Autodesk Fusion 360 part; units mm, degrees
(part 2 of 2)
equation "cass_t_Ref = 34 mm" comment "SOURCE: layout study B1 final list L-CASS 34 (tray + 25 gap + felt 9)"
equation "stack_t_Ref = outer_t_Ref + cav_gap_Ref + cass_t_Ref" comment "CALCULATION: D-16, D-42 stack, walls and ceiling: 46 + 4 + 34 = 84 (was 81 with outer_t 43); the inside is 3 mm smaller per wall and in height"
equation "wall_depth_Ref = 1495 mm" comment "DECIDED: PM ruling pass C: side walls start at the decor back plate (Y -645), as v1 (1496)"
equation "lin_gap_Ref = 4 mm" comment "ASSUMPTION: PM ruling pass C: gap above the upper side linings so they stay floating (= the 4 mm stack gap)"
equation "seam_gap_Ref = 2.26 mm" comment "DECIDED: PM ruling 2026-10-31 (Mechanical Checker F-001, F-005): the Joints Engineer's 2.26 mm at all nine site seam types, set by a metal stop (1.5 stop washer + 0.76 rivnut head; joints register section 2.8)"
equation "wall_z0_Ref = glide_h_Ref + band_h_Ref" comment "CALCULATION: base band top (Z 110)"
equation "panel_z0_Ref = wall_z0_Ref + seam_gap_Ref" comment "CALCULATION: walls stand one seam_gap above the band top (Z 112.26; joints register 2.8, IF-01)"
equation "wall_h_Ref = pod_h_Ref - wall_z0_Ref" comment "CALCULATION: 2290 = layout study v2_model wall_h"
equation "side_h_Ref = ( wall_h_Ref - 2 * seam_gap_Ref ) / 2" comment "CALCULATION: D-23: 2 sheets per side wall; the gap on the band and the horizontal seam (1142.74, was 1145; joints register 2.8)"
equation "pod_h_Ref1 = 2400 mm" comment "DECIDED: D-21 (room floor to roof skin top)"
equation "glide_h_Ref1 = 10 mm" comment "ASSUMPTION: layout study inputs.py glide_h"
equation "band_h_Ref1 = 100 mm" comment "SOURCE: layout study B1 list B-BAND 100x40; inputs.py base_h"
equation "outer_t_Ref1 = skin_t_Ref + bond_t_Ref + frame_t_Ref" comment "DECIDED: PM ruling 2026-10-31: ACP 3 + bond line 3 + frame 40, walls and ceiling (was 43)"
equation "seam_gap_Ref1 = 2.26 mm" comment "DECIDED: PM ruling 2026-10-31 (Mechanical Checker F-001, F-005): the Joints Engineer's 2.26 mm at all nine site seam types, set by a metal stop (1.5 stop washer + 0.76 rivnut head; joints register section 2.8)"
equation "wall_z0_Ref1 = glide_h_Ref1 + band_h_Ref1" comment "CALCULATION: base band top: glides + band"
equation "panel_z0_Ref1 = wall_z0_Ref1 + seam_gap_Ref1" comment "CALCULATION: walls stand one seam_gap above the band top (joints register 2.8, IF-01)"
equation "back_oh_Ref = pod_h_Ref1 - outer_t_Ref1 - seam_gap_Ref1 - panel_z0_Ref1" comment "CALCULATION: PM ruling 2026-10-31 (pass D, F-004): the back outer frames run up to the ceiling frame (pod_h - outer_t), less the seam_gap under it, closing the slot at the back top edge"
equation "back_ph_Ref = ( back_oh_Ref - seam_gap_Ref1 ) / 2" comment "CALCULATION: D-23: 4 sheets on the back, two equal rows with one seam_gap between them (joints register 2.8); the lower back linings match the lower row, as on the side walls"
equation "skin_t_Ref = 3 mm" comment "DECIDED: ACP skin, walls and ceiling (D-16; PM ruling 2026-10-31 on outer_t)"
equation "bond_t_Ref = 3 mm" comment "DECIDED: bond line between the ACP and the frame (PM ruling 2026-10-31 on outer_t)"
equation "frame_t_Ref = 40 mm" comment "DECIDED: aluminium frame tube depth, walls and ceiling (PM ruling 2026-10-31 on outer_t)"
equation "pod_h_Ref2 = 2400 mm" comment "DECIDED: D-21 (room floor to roof skin top)"
equation "outer_t_Ref2 = skin_t_Ref1 + bond_t_Ref1 + frame_t_Ref1" comment "DECIDED: PM ruling 2026-10-31: ACP 3 + bond line 3 + frame 40, walls and ceiling (was 43)"
equation "n_base_bolt_Ref = 4" comment "DECIDED: PM ruling 2026-10-31, J-BASE-01: bolts per panel along the band, evenly spaced"
equation "skin_t_Ref1 = 3 mm" comment "DECIDED: ACP skin, walls and ceiling (D-16; PM ruling 2026-10-31 on outer_t)"
equation "bond_t_Ref1 = 3 mm" comment "DECIDED: bond line between the ACP and the frame (PM ruling 2026-10-31 on outer_t)"
equation "frame_t_Ref1 = 40 mm" comment "DECIDED: aluminium frame tube depth, walls and ceiling (PM ruling 2026-10-31 on outer_t)"
equation "bolt_edge_inset_Ref = 220 mm" comment "DECIDED: PM ruling 2026-10-31: on every bolted edge the end bolts sit this far in from each panel end (the FRAME end, where the bolts go), the rest evenly spaced"
equation "spigot_inset_Ref = 100 mm" comment "DECIDED: PM ruling 2026-10-31: locating spigots this far in from each panel end (round hole at one end, slot at the other)"
equation "ceil_bolt_z_Ref = pod_h_Ref2 - outer_t_Ref2 + frame_t_Ref1 / 2" comment "DECIDED: PM ruling 2026-10-31, J-CEIL-01 wall to ceiling: the bolt line on the ceiling frame's centre (Z 2374)"
equation "pod_w = pod_w_Ref" comment "LINKED: pod_w_Ref, derived from 100000_P04_POD-SKELETON_CAD v4 (skeleton is the single source)"
equation "pod_d = pod_d_Ref" comment "LINKED: pod_d_Ref, derived from 100000_P04_POD-SKELETON_CAD v4 (skeleton is the single source)"
equation "pod_h = pod_h_Ref" comment "LINKED: pod_h_Ref, derived from 100000_P04_POD-SKELETON_CAD v4 (skeleton is the single source)"
equation "wall_depth = wall_depth_Ref" comment "LINKED: wall_depth_Ref, derived from 100000_P04_POD-SKELETON_CAD v4 (skeleton is the single source)"
equation "wall_z0 = wall_z0_Ref" comment "LINKED: wall_z0_Ref, derived from 100000_P04_POD-SKELETON_CAD v4 (skeleton is the single source)"
equation "panel_z0 = panel_z0_Ref" comment "LINKED: panel_z0_Ref, derived from 100000_P04_POD-SKELETON_CAD v4 (skeleton is the single source)"
equation "side_h = side_h_Ref" comment "LINKED: side_h_Ref, derived from 100000_P04_POD-SKELETON_CAD v4 (skeleton is the single source)"
equation "back_ph = back_ph_Ref" comment "LINKED: back_ph_Ref, derived from 100000_P04_POD-SKELETON_CAD v4 (skeleton is the single source)"
equation "stack_t = stack_t_Ref" comment "LINKED: stack_t_Ref, derived from 100000_P04_POD-SKELETON_CAD v4 (skeleton is the single source)"
equation "outer_t = outer_t_Ref" comment "LINKED: outer_t_Ref, derived from 100000_P04_POD-SKELETON_CAD v4 (skeleton is the single source)"
equation "cass_t = cass_t_Ref" comment "LINKED: cass_t_Ref, derived from 100000_P04_POD-SKELETON_CAD v4 (skeleton is the single source)"
equation "lin_gap = lin_gap_Ref" comment "LINKED: lin_gap_Ref, derived from 100000_P04_POD-SKELETON_CAD v4 (skeleton is the single source)"
equation "seam_gap = seam_gap_Ref" comment "LINKED: seam_gap_Ref, derived from 100000_P04_POD-SKELETON_CAD v4 (skeleton is the single source)"
equation "skin_t = skin_t_Ref" comment "LINKED: skin_t_Ref, derived from 100000_P04_POD-SKELETON_CAD v4 (skeleton is the single source)"
equation "bond_t = bond_t_Ref" comment "LINKED: bond_t_Ref, derived from 100000_P04_POD-SKELETON_CAD v4 (skeleton is the single source)"
equation "bolt_edge_inset = bolt_edge_inset_Ref" comment "LINKED: bolt_edge_inset_Ref, derived from 100000_P04_POD-SKELETON_CAD v4 (skeleton is the single source)"
equation "spigot_inset = spigot_inset_Ref" comment "LINKED: spigot_inset_Ref, derived from 100000_P04_POD-SKELETON_CAD v4 (skeleton is the single source)"
equation "n_base_bolt = n_base_bolt_Ref" comment "LINKED: n_base_bolt_Ref, derived from 100000_P04_POD-SKELETON_CAD v4 (skeleton is the single source)"
equation "ceil_bolt_z = ceil_bolt_z_Ref" comment "LINKED: ceil_bolt_z_Ref, derived from 100000_P04_POD-SKELETON_CAD v4 (skeleton is the single source)"
equation "tube_w = 20 mm" comment "CONFIRMED: D-34, D-54: aluminium tube 20 x 40 x 1.2; the 20 mm face carries the skin, so the 40 mm runs through the wall (outer_t = ACP 3 + frame 40). The joint register may turn it for the bond width (HOLD)"
equation "tube_d = outer_t - skin_t - bond_t" comment "CALCULATION: frame depth = outer panel 46 - skin 3 - bond 3 = 40 (D-34)"
equation "tube_t = 1.2 mm" comment "CONFIRMED: D-34, D-54, D-85: perimeter members (rails, front and back stiles) keep the 1.2 mm wall; they carry the rivnuts (grip check passed)"
equation "stud_t = 1.0 mm" comment "CONFIRMED: D-85 (weight): intermediate studs at a 1.0 mm wall; they carry no rivnut, only the skin's bond line"
equation "stile_pitch_max = 400 mm" comment "CONFIRMED: D-16, D-34: members 400 mm apart or less, to keep the ACP flat"
equation "pnl_len = wall_depth - seam_gap" comment "CALCULATION: D-49 depth 1495 less the 2.26 gap at the decor back plate (PM ruling on F-008): 1492.74"
equation "pnl_h = side_h" comment "CALCULATION: skeleton side_h: 2 sheets per side wall (D-23) with the seam gaps"
equation "skin_ret = outer_t - skin_t" comment "ASSUMPTION: back return of the side skin: covers the frame's back end at the corner, where the side skin covers the back panel's edge (D-55; sample drawing D04). V-groove and fold per the ACP maker (HOLD H16)"
equation "skin_setback = 0 mm" comment "ASSUMPTION: skin edge set back from the frame's top and bottom edges: 0, so the outside reveal equals the 2.26 seam gap (D-23: crisp, aligned reveals; joints register 2.8 leaves the setback to the WALL drawing)"
equation "frm_len = pnl_len - skin_t" comment "CALCULATION: the frame stops at the inside of the skin's back return"
equation "frm_h = pnl_h" comment "ASSUMPTION: the frame fills the skeleton envelope height; seam and base gasket gaps are set by the joint register (HOLD)"
equation "corner_w = 40 mm" comment "CONFIRMED: the side panel's back member is 40 x 40 x 1.2 (PM ruling on the joints register, item 3, 2026-10-31; register F2, FR-06): the back corner joint needs a 37+ mm overlap for the rivnut and the bolt"
equation "stile_n_mid = ceil(( frm_len - tube_w / 2 - corner_w / 2 ) / stile_pitch_max) - 1" comment "CALCULATION: intermediate stiles so that no stile pitch (centre to centre) exceeds stile_pitch_max"
equation "stile_pitch = ( frm_len - tube_w / 2 - corner_w / 2 ) / ( stile_n_mid + 1 )" comment "CALCULATION: equal stile pitch, centre to centre, from the front stile to the 40 mm back stile"
equation "top_h = tube_w" comment "CALCULATION: top member height: 20 on a lower panel; 40 x 40 on an upper panel, where the ceiling bolts in (PM ruling R-J3, joints register FR-06)"
equation "stile_len = frm_h - tube_w - top_h" comment "CALCULATION: stiles fit between the full-length rails (butt joints)"
equation "ceil_bolt_dz = pod_h - ceil_bolt_z" comment "CALCULATION: J-CEIL-01 side bolts on the ceiling frame tube's centre: the skeleton's ceil_bolt_z, Z 2374 on P04 (joints register R-J15, FR-07)"
equation "fill_t = tube_d" comment "CALCULATION: 40 mm PET fill fills the frame depth (D-34; layout study 40 mm)"
equation "bolt_d = 7 mm" comment "CONFIRMED: PM ruling on F-009: bolt holes 7.0 (0.51 float), position tolerance 0.4 (+-0.2) from the spigot hole, CNC or drill jig (joints register FR-02)"
equation "access_d = 19 mm" comment "CALCULATION: register FR-03: passes the 18 mm head washer (ISO 7093-1, R-J10), the M6 head and the 5 mm key; holds the grommet retainer (H-02)"
equation "bolt_line_y = pod_d / 2 - skin_t - bond_t - tube_d / 2" comment "CONFIRMED: J-WALL-02 bolt line on the back panel's tube centre, Y 824 (joints register R-J15, FR-07)"
equation "rivnut_d = 9.53 mm" comment "SOURCE: Sherex CAH3-610-4.2 hole 9.53 +0.10 (HW-SEL A5; register H-03)"
equation "spigot_d = 8.5 mm" comment "ASSUMPTION: register FR-05: hole for the 8 mm locating spigot H-05"
equation "spigot_slot = 14 mm" comment "ASSUMPTION: register FR-05: slot length for the second spigot"
equation "spigot_edge = spigot_inset" comment "CALCULATION: the skeleton's spigot_inset: spigots 100 from each end of the edge (PM ruling 2026-10-31, R-J13)"
equation "bolt_edge = bolt_edge_inset" comment "CALCULATION: the skeleton's bolt_edge_inset: end bolts 220 in from the panel's ends, evenly spaced, every bolt 30 or more from any stile (PM ruling 2026-10-31, R-J14)"
equation "n_side_jnt = 3" comment "SOURCE: register J-WALL-02, J-FRONT-01: 3 bolts up each side panel"
equation "side_jnt_pitch = ( pnl_h - 2 * bolt_edge ) / ( n_side_jnt - 1 )" comment "CALCULATION: equal pitch of the 3 bolts up the corner and decor joints"
equation "pocket_w = 60 mm" comment "ASSUMPTION: register FR-10: fill left out 60 x 60 next to each bolt for the key"
equation "corner_z0 = panel_z0" comment "CALCULATION: bottom of the back panel row this side panel meets at the corner (B1/B2 or B3/B4, skeleton P04)"
equation "corner_bolt_pitch = ( back_ph - 2 * bolt_edge ) / ( n_side_jnt - 1 )" comment "CALCULATION: J-WALL-02 bolts run along the back panel's edge: 220, 559.31, 898.61 on its 1118.61 (joints register 2.9)"
equation "n_len_bolt = n_base_bolt" comment "CALCULATION: the skeleton's n_base_bolt (4): the same count on J-WALL-01 and the J-CEIL-01 side edges (register 2.9)"
equation "ceil_bolt_pitch = ( wall_depth - 2 * bolt_edge ) / ( n_len_bolt - 1 )" comment "CALCULATION: J-CEIL-01 side edge: 4 bolts along the ceiling's 1495 from Y -645 (its front edge), 220 rule, pitch 351.67 on P04; CEILING drills the same (PM ruling 2026-10-31 16:55; joints register 2.9)"
equation "len_bolt_pitch = ( pnl_len - 2 * bolt_edge ) / ( n_len_bolt - 1 )" comment "CALCULATION: even pitch of the bolts along the panel"
equation "felt_t = 9 mm" comment "SOURCE: plan VT03-PET 9 mm PET felt; HW-SEL A3; D-31 (the factory's felt)"
equation "tray_t = 0.5 mm" comment "CONFIRMED: D-37: galvanised steel tray 0.5 mm"
equation "tray_h = cass_t" comment "CONFIRMED: PM ruling 2026-10-31 (WALL group, option 1): the wall cassettes use the ceiling's tray, returns the full cassette depth (34) turned in as lips that hold the felt, no ribs; settles H09 for the walls"
equation "lip_w = 12 mm" comment "CONFIRMED: PM ruling 2026-10-31 (WALL group, option 1): 12 mm lips hold the felt edge"
equation "bend_r = tray_t" comment "ASSUMPTION: inside bend radius 1 x t for 0.5 mm DX51D (the sheet metal rule's bend radius is its Thickness); the factory's tooling sets it (guideline 9)"
equation "felt_c = 1 mm" comment "ASSUMPTION: felt edge clearance inside the returns, as the ceiling cassette"
equation "gap_h = tray_h - felt_t - 2 * tray_t" comment "CALCULATION: air gap between the tray base and the felt (24): the acoustic gap (D-17) and the cable path (D-26)"
equation "cass_len = wall_depth - stack_t + cass_t" comment "CALCULATION: = 1448: from the decor back plate to past the back cassette's face, closing the inside corner (D-57)"
equation "cass_h = side_h" comment "CALCULATION: lower: the panel height; upper: stops lin_gap under the roof frame so it floats (D-57)"
equation "clip_zone_h = 60 mm" comment "ASSUMPTION: height of each reserved clip zone (H03: no clip named)"
equation "clip_zone_dz = 100 mm" comment "ASSUMPTION: clip zone centre from the cassette's top and bottom edges (H03)"
equation "stopw_od = 20 mm" comment "SOURCE: joints register H-08: stop washer Ø10.5 x Ø20 x 1.5 (PROPOSED part)"
equation "stopw_id = 10.5 mm" comment "SOURCE: joints register H-08"
equation "stopw_t = 1.5 mm" comment "SOURCE: joints register H-08: rivnut head 0.76 + washer 1.5 = the 2.26 stop (R-J5)"
equation "rivnut_head_d = 12.96 mm" comment "SOURCE: Sherex CAH3-610-4.2 head Ø12.96 (joints register H-03, SHX)"
equation "rivnut_head_t = 0.76 mm" comment "SOURCE: Sherex CAH3-610-4.2 head 0.76 ±0.08 (H-03, SHX)"
equation "rivnut_body_d = 9.5 mm" comment "SOURCE: Sherex CAH3-610-4.2 body Ø9.50 max (H-03, SHX)"
equation "rivnut_len = 10.16 mm" comment "SOURCE: Sherex CAH3-610-4.2 installed length 10.16 max under the head (H-03, SHX); the bulge inside the tube is not modelled"
equation "m6_d = 6 mm" comment "CALCULATION: M6 threads shown at their 6 mm major diameter (no modelled thread)"
equation "spigot_pin_d = 8 mm" comment "SOURCE: joints register H-05: Ø8 stainless pin (PROPOSED, assumption sizes)"
equation "spigot_proud = 8 mm" comment "SOURCE: joints register H-05: stands 8 proud (read as: of the joint face)"
equation "spigot_thread_l = 10 mm" comment "ASSUMPTION: M6 thread into the spigot rivnut; H-05 gives no length; 10 stays inside the rivnut's 10.16"
equation "d1744 = panel_z0"
equation "d1746 = ( -( pod_w / 2 - outer_t ) ) - ( -( pod_w / 2 - skin_t - bond_t ) )"
equation "d1747 = ( pod_d / 2 - skin_t ) - ( pod_d / 2 - wall_depth + seam_gap )"
equation "d1748 = abs(-( pod_w / 2 - skin_t - bond_t ))"
equation "d1749 = abs(pod_d / 2 - wall_depth + seam_gap)"
equation "d1750 = ( ( panel_z0 ) + tube_w ) - ( panel_z0 )"
equation "d1752 = ( panel_z0 ) + tube_t"
equation "d1754 = ( ( -( pod_w / 2 - outer_t ) ) - tube_t ) - ( ( -( pod_w / 2 - skin_t - bond_t ) ) + tube_t )"
equation "d1755 = ( pod_d / 2 - skin_t ) - ( pod_d / 2 - wall_depth + seam_gap )"
equation "d1756 = abs(( -( pod_w / 2 - skin_t - bond_t ) ) + tube_t)"
equation "d1757 = abs(pod_d / 2 - wall_depth + seam_gap)"
equation "d1758 = ( ( ( panel_z0 ) + tube_w ) - tube_t ) - ( ( panel_z0 ) + tube_t )"
equation "d1760 = ( panel_z0 + side_h ) - top_h"
equation "d1762 = ( -( pod_w / 2 - outer_t ) ) - ( -( pod_w / 2 - skin_t - bond_t ) )"
equation "d1763 = ( pod_d / 2 - skin_t ) - ( pod_d / 2 - wall_depth + seam_gap )"
equation "d1764 = abs(-( pod_w / 2 - skin_t - bond_t ))"
equation "d1765 = abs(pod_d / 2 - wall_depth + seam_gap)"
equation "d1766 = ( panel_z0 + side_h ) - ( ( panel_z0 + side_h ) - top_h )"
equation "d1768 = ( ( panel_z0 + side_h ) - top_h ) + tube_t"
equation "d1770 = ( ( -( pod_w / 2 - outer_t ) ) - tube_t ) - ( ( -( pod_w / 2 - skin_t - bond_t ) ) + tube_t )"
equation "d1771 = ( pod_d / 2 - skin_t ) - ( pod_d / 2 - wall_depth + seam_gap )"
equation "d1772 = abs(( -( pod_w / 2 - skin_t - bond_t ) ) + tube_t)"
equation "d1773 = abs(pod_d / 2 - wall_depth + seam_gap)"
equation "d1774 = ( ( panel_z0 + side_h ) - tube_t ) - ( ( ( panel_z0 + side_h ) - top_h ) + tube_t )"
equation "d1776 = ( panel_z0 ) + tube_w"
equation "d1778 = ( -( pod_w / 2 - outer_t ) ) - ( -( pod_w / 2 - skin_t - bond_t ) )"
equation "d1779 = ( ( pod_d / 2 - wall_depth + seam_gap ) + tube_w ) - ( pod_d / 2 - wall_depth + seam_gap )"
equation "d1780 = abs(-( pod_w / 2 - skin_t - bond_t ))"
equation "d1781 = abs(pod_d / 2 - wall_depth + seam_gap)"
equation "d1782 = ( ( panel_z0 + side_h ) - top_h ) - ( ( panel_z0 ) + tube_w )"
equation "d1784 = ( panel_z0 ) + tube_w"
equation "d1786 = ( ( -( pod_w / 2 - outer_t ) ) - tube_t ) - ( ( -( pod_w / 2 - skin_t - bond_t ) ) + tube_t )"
equation "d1787 = ( ( ( pod_d / 2 - wall_depth + seam_gap ) + tube_w ) - tube_t ) - ( ( pod_d / 2 - wall_depth + seam_gap ) + tube_t )"
equation "d1788 = abs(( -( pod_w / 2 - skin_t - bond_t ) ) + tube_t)"
equation "d1789 = abs(( pod_d / 2 - wall_depth + seam_gap ) + tube_t)"
equation "d1790 = ( ( panel_z0 + side_h ) - top_h ) - ( ( panel_z0 ) + tube_w )"
equation "d1792 = ( panel_z0 ) + tube_w"
equation "d1794 = ( -( pod_w / 2 - outer_t ) ) - ( -( pod_w / 2 - skin_t - bond_t ) )"
equation "d1795 = ( pod_d / 2 - skin_t ) - ( ( pod_d / 2 - skin_t ) - corner_w )"
equation "d1796 = abs(-( pod_w / 2 - skin_t - bond_t ))"
equation "d1797 = abs(( pod_d / 2 - skin_t ) - corner_w)"
equation "d1798 = ( ( panel_z0 + side_h ) - top_h ) - ( ( panel_z0 ) + tube_w )"
equation "d1800 = ( panel_z0 ) + tube_w"
equation "d1802 = ( ( -( pod_w / 2 - outer_t ) ) - tube_t ) - ( ( -( pod_w / 2 - skin_t - bond_t ) ) + tube_t )"
equation "d1803 = ( ( pod_d / 2 - skin_t ) - tube_t ) - ( ( ( pod_d / 2 - skin_t ) - corner_w ) + tube_t )"
equation "d1804 = abs(( -( pod_w / 2 - skin_t - bond_t ) ) + tube_t)"
equation "d1805 = abs(( ( pod_d / 2 - skin_t ) - corner_w ) + tube_t)"
equation "d1806 = ( ( panel_z0 + side_h ) - top_h ) - ( ( panel_z0 ) + tube_w )"
equation "d1808 = ( panel_z0 ) + tube_w"
equation "d1810 = ( -( pod_w / 2 - outer_t ) ) - ( -( pod_w / 2 - skin_t - bond_t ) )"
equation "d1811 = ( ( pod_d / 2 - wall_depth + seam_gap ) + stile_pitch + tube_w ) - ( ( pod_d / 2 - wall_depth + seam_gap ) + stile_pitch )"
equation "d1812 = abs(-( pod_w / 2 - skin_t - bond_t ))"
equation "d1813 = abs(( pod_d / 2 - wall_depth + seam_gap ) + stile_pitch)"
equation "d1814 = ( ( panel_z0 + side_h ) - top_h ) - ( ( panel_z0 ) + tube_w )"
equation "d1816 = ( panel_z0 ) + tube_w"
equation "d1818 = ( ( -( pod_w / 2 - outer_t ) ) - stud_t ) - ( ( -( pod_w / 2 - skin_t - bond_t ) ) + stud_t )"
equation "d1819 = ( ( ( pod_d / 2 - wall_depth + seam_gap ) + stile_pitch + tube_w ) - stud_t ) - ( ( ( pod_d / 2 - wall_depth + seam_gap ) + stile_pitch ) + stud_t )"
equation "d1820 = abs(( -( pod_w / 2 - skin_t - bond_t ) ) + stud_t)"
equation "d1821 = abs(( ( pod_d / 2 - wall_depth + seam_gap ) + stile_pitch ) + stud_t)"
equation "d1822 = ( ( panel_z0 + side_h ) - top_h ) - ( ( panel_z0 ) + tube_w )"
equation "d1824 = stile_n_mid"
equation "d1826 = stile_pitch"
equation "d1828 = ( panel_z0 ) + skin_setback"
equation "d1830 = ( -( pod_w / 2 - skin_t ) ) - ( -( pod_w / 2 ) )"
equation "d1831 = ( pod_d / 2 ) - ( pod_d / 2 - wall_depth + seam_gap )"
equation "d1832 = abs(-( pod_w / 2 ))"
equation "d1833 = abs(pod_d / 2 - wall_depth + seam_gap)"
equation "d1834 = ( ( panel_z0 + side_h ) - skin_setback ) - ( ( panel_z0 ) + skin_setback )"
equation "d1836 = ( panel_z0 ) + skin_setback"
equation "d1838 = ( -( pod_w / 2 - skin_t - skin_ret ) ) - ( -( pod_w / 2 - skin_t ) )"
equation "d1839 = ( pod_d / 2 ) - ( pod_d / 2 - skin_t )"
equation "d1840 = abs(-( pod_w / 2 - skin_t ))"
equation "d1841 = abs(pod_d / 2 - skin_t)"
equation "d1842 = ( ( panel_z0 + side_h ) - skin_setback ) - ( ( panel_z0 ) + skin_setback )"
equation "d1844 = ( panel_z0 ) + tube_w"
equation "d1846 = ( -( pod_w / 2 - outer_t ) ) - ( -( pod_w / 2 - skin_t - bond_t ) )"
equation "d1847 = ( ( pod_d / 2 - wall_depth + seam_gap ) + stile_pitch ) - ( ( pod_d / 2 - wall_depth + seam_gap ) + tube_w )"
equation "d1848 = abs(-( pod_w / 2 - skin_t - bond_t ))"
equation "d1849 = abs(( pod_d / 2 - wall_depth + seam_gap ) + tube_w)"
equation "d1850 = ( ( panel_z0 + side_h ) - top_h ) - ( ( panel_z0 ) + tube_w )"
equation "d1852 = stile_n_mid"
equation "d1854 = stile_pitch"
equation "d1856 = ( panel_z0 ) + tube_w"
equation "d1858 = ( -( pod_w / 2 - outer_t ) ) - ( -( pod_w / 2 - skin_t - bond_t ) )"
equation "d1859 = ( ( pod_d / 2 - skin_t ) - corner_w ) - ( ( pod_d / 2 - wall_depth + seam_gap ) + stile_n_mid * stile_pitch + tube_w )"
equation "d1860 = abs(-( pod_w / 2 - skin_t - bond_t ))"
equation "d1861 = abs(( pod_d / 2 - wall_depth + seam_gap ) + stile_n_mid * stile_pitch + tube_w)"
equation "d1862 = ( ( panel_z0 + side_h ) - top_h ) - ( ( panel_z0 ) + tube_w )"
equation "d1864 = ( panel_z0 ) + tube_w"
equation "d1866 = ( -( pod_w / 2 - outer_t ) ) - ( -( pod_w / 2 - skin_t - bond_t ) )"
equation "d1867 = ( ( ( pod_d / 2 - wall_depth + seam_gap ) + bolt_edge + 0 * len_bolt_pitch ) + pocket_w / 2 ) - ( ( ( pod_d / 2 - wall_depth + seam_gap ) + bolt_edge + 0 * len_bolt_pitch ) - pocket_w / 2 )"
equation "d1868 = abs(-( pod_w / 2 - skin_t - bond_t ))"
equation "d1869 = abs(( ( pod_d / 2 - wall_depth + seam_gap ) + bolt_edge + 0 * len_bolt_pitch ) - pocket_w / 2)"
equation "d1870 = ( ( ( panel_z0 ) + tube_w ) + pocket_w ) - ( ( panel_z0 ) + tube_w )"
equation "d1872 = ( panel_z0 ) + tube_w"
equation "d1874 = ( -( pod_w / 2 - outer_t ) ) - ( -( pod_w / 2 - skin_t - bond_t ) )"
equation "d1875 = ( ( ( pod_d / 2 - wall_depth + seam_gap ) + bolt_edge + 1 * len_bolt_pitch ) + pocket_w / 2 ) - ( ( ( pod_d / 2 - wall_depth + seam_gap ) + bolt_edge + 1 * len_bolt_pitch ) - pocket_w / 2 )"
equation "d1876 = abs(-( pod_w / 2 - skin_t - bond_t ))"
equation "d1877 = abs(( ( pod_d / 2 - wall_depth + seam_gap ) + bolt_edge + 1 * len_bolt_pitch ) - pocket_w / 2)"
equation "d1878 = ( ( ( panel_z0 ) + tube_w ) + pocket_w ) - ( ( panel_z0 ) + tube_w )"
equation "d1880 = ( panel_z0 ) + tube_w"
equation "d1882 = ( -( pod_w / 2 - outer_t ) ) - ( -( pod_w / 2 - skin_t - bond_t ) )"
equation "d1883 = ( ( ( pod_d / 2 - wall_depth + seam_gap ) + bolt_edge + 2 * len_bolt_pitch ) + pocket_w / 2 ) - ( ( ( pod_d / 2 - wall_depth + seam_gap ) + bolt_edge + 2 * len_bolt_pitch ) - pocket_w / 2 )"
equation "d1884 = abs(-( pod_w / 2 - skin_t - bond_t ))"
equation "d1885 = abs(( ( pod_d / 2 - wall_depth + seam_gap ) + bolt_edge + 2 * len_bolt_pitch ) - pocket_w / 2)"
equation "d1886 = ( ( ( panel_z0 ) + tube_w ) + pocket_w ) - ( ( panel_z0 ) + tube_w )"
equation "d1888 = ( panel_z0 ) + tube_w"
equation "d1890 = ( -( pod_w / 2 - outer_t ) ) - ( -( pod_w / 2 - skin_t - bond_t ) )"
equation "d1891 = ( ( ( pod_d / 2 - wall_depth + seam_gap ) + bolt_edge + 3 * len_bolt_pitch ) + pocket_w / 2 ) - ( ( ( pod_d / 2 - wall_depth + seam_gap ) + bolt_edge + 3 * len_bolt_pitch ) - pocket_w / 2 )"
equation "d1892 = abs(-( pod_w / 2 - skin_t - bond_t ))"
equation "d1893 = abs(( ( pod_d / 2 - wall_depth + seam_gap ) + bolt_edge + 3 * len_bolt_pitch ) - pocket_w / 2)"
equation "d1894 = ( ( ( panel_z0 ) + tube_w ) + pocket_w ) - ( ( panel_z0 ) + tube_w )"
equation "d1896 = ( ( ( panel_z0 ) + bolt_edge ) + 0 * side_jnt_pitch ) - pocket_w / 2"
equation "d1898 = ( -( pod_w / 2 - outer_t ) ) - ( -( pod_w / 2 - skin_t - bond_t ) )"
equation "d1899 = ( ( pod_d / 2 - wall_depth + seam_gap ) + tube_w + pocket_w ) - ( ( pod_d / 2 - wall_depth + seam_gap ) + tube_w )"
equation "d1900 = abs(-( pod_w / 2 - skin_t - bond_t ))"
equation "d1901 = abs(( pod_d / 2 - wall_depth + seam_gap ) + tube_w)"
equation "d1902 = ( ( ( ( panel_z0 ) + bolt_edge ) + 0 * side_jnt_pitch ) + pocket_w / 2 ) - ( ( ( ( panel_z0 ) + bolt_edge ) + 0 * side_jnt_pitch ) - pocket_w / 2 )"
equation "d1904 = ( ( ( panel_z0 ) + bolt_edge ) + 1 * side_jnt_pitch ) - pocket_w / 2"
equation "d1906 = ( -( pod_w / 2 - outer_t ) ) - ( -( pod_w / 2 - skin_t - bond_t ) )"
equation "d1907 = ( ( pod_d / 2 - wall_depth + seam_gap ) + tube_w + pocket_w ) - ( ( pod_d / 2 - wall_depth + seam_gap ) + tube_w )"
equation "d1908 = abs(-( pod_w / 2 - skin_t - bond_t ))"
equation "d1909 = abs(( pod_d / 2 - wall_depth + seam_gap ) + tube_w)"
equation "d1910 = ( ( ( ( panel_z0 ) + bolt_edge ) + 1 * side_jnt_pitch ) + pocket_w / 2 ) - ( ( ( ( panel_z0 ) + bolt_edge ) + 1 * side_jnt_pitch ) - pocket_w / 2 )"
equation "d1912 = ( ( ( panel_z0 ) + bolt_edge ) + 2 * side_jnt_pitch ) - pocket_w / 2"
equation "d1914 = ( -( pod_w / 2 - outer_t ) ) - ( -( pod_w / 2 - skin_t - bond_t ) )"
equation "d1915 = ( ( pod_d / 2 - wall_depth + seam_gap ) + tube_w + pocket_w ) - ( ( pod_d / 2 - wall_depth + seam_gap ) + tube_w )"
equation "d1916 = abs(-( pod_w / 2 - skin_t - bond_t ))"
equation "d1917 = abs(( pod_d / 2 - wall_depth + seam_gap ) + tube_w)"
equation "d1918 = ( ( ( ( panel_z0 ) + bolt_edge ) + 2 * side_jnt_pitch ) + pocket_w / 2 ) - ( ( ( ( panel_z0 ) + bolt_edge ) + 2 * side_jnt_pitch ) - pocket_w / 2 )"
equation "d1920 = panel_z0"
equation "d1922 = abs(-( pod_w / 2 - skin_t - bond_t - tube_d / 2 ))"
equation "d1923 = abs(( pod_d / 2 - wall_depth + seam_gap ) + bolt_edge)"
equation "d1924 = tube_t"
equation "d1925 = bolt_d"
equation "d1927 = ( panel_z0 ) + tube_w"
equation "d1929 = abs(-( pod_w / 2 - skin_t - bond_t - tube_d / 2 ))"
equation "d1930 = abs(( pod_d / 2 - wall_depth + seam_gap ) + bolt_edge)"
equation "d1931 = tube_t"
equation "d1932 = access_d"
equation "d1934 = n_len_bolt"
equation "d1936 = len_bolt_pitch"
equation "d1938 = panel_z0"
equation "d1940 = abs(-( pod_w / 2 - skin_t - bond_t - tube_d / 2 ))"
equation "d1941 = abs(( pod_d / 2 - wall_depth + seam_gap ) + spigot_edge)"
equation "d1942 = tube_t"
equation "d1943 = spigot_d"
equation "d1945 = panel_z0"
equation "d1947 = ( ( -( pod_w / 2 - skin_t - bond_t - tube_d / 2 ) ) + ( spigot_slot - spigot_d ) / 2 ) - ( ( -( pod_w / 2 - skin_t - bond_t - tube_d / 2 ) ) - ( spigot_slot - spigot_d ) / 2 )"
equation "d1948 = ( ( ( pod_d / 2 ) - spigot_edge ) + spigot_d / 2 ) - ( ( ( pod_d / 2 ) - spigot_edge ) - spigot_d / 2 )"
equation "d1949 = abs(( -( pod_w / 2 - skin_t - bond_t - tube_d / 2 ) ) - ( spigot_slot - spigot_d ) / 2)"
equation "d1950 = abs(( ( pod_d / 2 ) - spigot_edge ) - spigot_d / 2)"
equation "d1951 = ( ( panel_z0 ) + tube_t ) - ( panel_z0 )"
equation "d1953 = panel_z0"
equation "d1955 = abs(( -( pod_w / 2 - skin_t - bond_t - tube_d / 2 ) ) - ( spigot_slot - spigot_d ) / 2)"
equation "d1956 = abs(( pod_d / 2 ) - spigot_edge)"
equation "d1957 = tube_t"
equation "d1958 = spigot_d"
equation "d1960 = panel_z0"
equation "d1962 = abs(( -( pod_w / 2 - skin_t - bond_t - tube_d / 2 ) ) + ( spigot_slot - spigot_d ) / 2)"
equation "d1963 = abs(( pod_d / 2 ) - spigot_edge)"
equation "d1964 = tube_t"
equation "d1965 = spigot_d"
equation "d1967 = panel_z0 + side_h"
equation "d1969 = abs(-( pod_w / 2 - skin_t - bond_t - tube_d / 2 ))"
equation "d1970 = abs(( pod_d / 2 - wall_depth + seam_gap ) + bolt_edge)"
equation "d1971 = tube_t"
equation "d1972 = rivnut_d"
equation "d1974 = n_len_bolt"
equation "d1976 = len_bolt_pitch"
equation "d1978 = panel_z0 + side_h"
equation "d1980 = abs(-( pod_w / 2 - skin_t - bond_t - tube_d / 2 ))"
equation "d1981 = abs(( pod_d / 2 - wall_depth + seam_gap ) + spigot_edge)"
equation "d1982 = tube_t"
equation "d1983 = rivnut_d"
equation "d1985 = panel_z0 + side_h"
equation "d1987 = abs(-( pod_w / 2 - skin_t - bond_t - tube_d / 2 ))"
equation "d1988 = abs(( pod_d / 2 ) - spigot_edge)"
equation "d1989 = tube_t"
equation "d1990 = rivnut_d"
equation "d1992 = pod_d / 2 - wall_depth + seam_gap"
equation "d1994 = abs(-( pod_w / 2 - skin_t - bond_t - tube_d / 2 ))"
equation "d1995 = abs(( panel_z0 ) + bolt_edge)"
equation "d1996 = tube_t"
equation "d1997 = bolt_d"
equation "d1999 = ( pod_d / 2 - wall_depth + seam_gap ) + tube_w"
equation "d2001 = abs(-( pod_w / 2 - skin_t - bond_t - tube_d / 2 ))"
equation "d2002 = abs(( panel_z0 ) + bolt_edge)"
equation "d2003 = tube_t"
equation "d2004 = access_d"
equation "d2006 = n_side_jnt"
equation "d2008 = side_jnt_pitch"
equation "d2010 = -( pod_w / 2 - outer_t )"
equation "d2012 = abs(bolt_line_y)"
equation "d2013 = abs(corner_z0 + bolt_edge)"
equation "d2014 = tube_t"
equation "d2015 = rivnut_d"
equation "d2017 = n_side_jnt"
equation "d2019 = corner_bolt_pitch"
equation "d2021 = panel_z0 + side_h"
equation "d2023 = abs(-( pod_w / 2 - skin_t - bond_t - tube_d / 2 ))"
equation "d2024 = abs(( pod_d / 2 - wall_depth + seam_gap ) + bolt_edge)"
equation "d2025 = stopw_od"
equation "d2026 = stopw_id"
equation "d2027 = stopw_t"
equation "d2029 = ( panel_z0 + side_h ) + stopw_t"
equation "d2031 = abs(-( pod_w / 2 - skin_t - bond_t - tube_d / 2 ))"
equation "d2032 = abs(( pod_d / 2 - wall_depth + seam_gap ) + bolt_edge)"
equation "d2033 = rivnut_head_d"
equation "d2034 = m6_d"
equation "d2035 = rivnut_head_t"
equation "d2037 = ( panel_z0 + side_h ) + stopw_t"
equation "d2039 = abs(-( pod_w / 2 - skin_t - bond_t - tube_d / 2 ))"
equation "d2040 = abs(( pod_d / 2 - wall_depth + seam_gap ) + bolt_edge)"
equation "d2041 = rivnut_body_d"
equation "d2042 = m6_d"
equation "d2045 = -( rivnut_len )"
equation "d2047 = n_len_bolt"
equation "d2049 = len_bolt_pitch"
equation "d2051 = n_len_bolt"
equation "d2053 = len_bolt_pitch"
equation "d2055 = panel_z0 + side_h"
equation "d2057 = abs(-( pod_w / 2 - skin_t - bond_t - tube_d / 2 ))"
equation "d2058 = abs(( pod_d / 2 - wall_depth + seam_gap ) + spigot_edge)"
equation "d2059 = rivnut_head_d"
equation "d2060 = m6_d"
equation "d2061 = rivnut_head_t"
equation "d2063 = panel_z0 + side_h"
equation "d2065 = abs(-( pod_w / 2 - skin_t - bond_t - tube_d / 2 ))"
equation "d2066 = abs(( pod_d / 2 - wall_depth + seam_gap ) + spigot_edge)"
equation "d2067 = rivnut_body_d"
equation "d2068 = m6_d"
equation "d2071 = -( rivnut_len )"
equation "d2073 = ( panel_z0 + side_h ) + rivnut_head_t"
equation "d2075 = abs(-( pod_w / 2 - skin_t - bond_t - tube_d / 2 ))"
equation "d2076 = abs(( pod_d / 2 - wall_depth + seam_gap ) + spigot_edge)"
equation "d2077 = spigot_pin_d"
equation "d2078 = spigot_proud - rivnut_head_t"
equation "d2080 = ( panel_z0 + side_h ) + rivnut_head_t"
equation "d2082 = abs(-( pod_w / 2 - skin_t - bond_t - tube_d / 2 ))"
equation "d2083 = abs(( pod_d / 2 - wall_depth + seam_gap ) + spigot_edge)"
equation "d2084 = m6_d"
equation "d2087 = -( spigot_thread_l )"
equation "d2089 = panel_z0 + side_h"
equation "d2091 = abs(-( pod_w / 2 - skin_t - bond_t - tube_d / 2 ))"
equation "d2092 = abs(( pod_d / 2 ) - spigot_edge)"
equation "d2093 = rivnut_head_d"
equation "d2094 = m6_d"
equation "d2095 = rivnut_head_t"
equation "d2097 = panel_z0 + side_h"
equation "d2099 = abs(-( pod_w / 2 - skin_t - bond_t - tube_d / 2 ))"
equation "d2100 = abs(( pod_d / 2 ) - spigot_edge)"
equation "d2101 = rivnut_body_d"
equation "d2102 = m6_d"
equation "d2105 = -( rivnut_len )"
equation "d2107 = ( panel_z0 + side_h ) + rivnut_head_t"
equation "d2109 = abs(-( pod_w / 2 - skin_t - bond_t - tube_d / 2 ))"
equation "d2110 = abs(( pod_d / 2 ) - spigot_edge)"
equation "d2111 = spigot_pin_d"
equation "d2112 = spigot_proud - rivnut_head_t"
equation "d2114 = ( panel_z0 + side_h ) + rivnut_head_t"
equation "d2116 = abs(-( pod_w / 2 - skin_t - bond_t - tube_d / 2 ))"
equation "d2117 = abs(( pod_d / 2 ) - spigot_edge)"
equation "d2118 = m6_d"
equation "d2121 = -( spigot_thread_l )"
equation "d2123 = -( pod_w / 2 - outer_t )"
equation "d2125 = abs(bolt_line_y)"
equation "d2126 = abs(corner_z0 + bolt_edge)"
equation "d2127 = stopw_od"
equation "d2128 = stopw_id"
equation "d2129 = stopw_t"
equation "d2131 = ( -( pod_w / 2 - outer_t ) ) + stopw_t"
equation "d2133 = abs(bolt_line_y)"
equation "d2134 = abs(corner_z0 + bolt_edge)"
equation "d2135 = rivnut_head_d"
equation "d2136 = m6_d"
equation "d2137 = rivnut_head_t"
equation "d2139 = ( -( pod_w / 2 - outer_t ) ) + stopw_t"
equation "d2141 = abs(bolt_line_y)"
equation "d2142 = abs(corner_z0 + bolt_edge)"
equation "d2143 = rivnut_body_d"
equation "d2144 = m6_d"
equation "d2147 = -( rivnut_len )"
equation "d2149 = n_side_jnt"
equation "d2151 = corner_bolt_pitch"
equation "d2153 = n_side_jnt"
equation "d2155 = corner_bolt_pitch"
named bodies: "RAIL - BOTTOM", "RAIL - TOP", "STILE - FRONT", "STILE - BACK", "STILE - MID 1", "STILE - MID 2", "STILE - MID 3", "SKIN - ACP 3 WITH BACK RETURN", "FILL - BAY 1", "FILL - BAY 2", "FILL - BAY 3", "FILL - BAY 4", "STOP WASHER - TOP RAIL 1", "RIVNUT - TOP RAIL 1", "STOP WASHER - TOP RAIL 2", "STOP WASHER - TOP RAIL 3", "STOP WASHER - TOP RAIL 4", "RIVNUT - TOP RAIL 2", "RIVNUT - TOP RAIL 3", "RIVNUT - TOP RAIL 4", "RIVNUT - TOP RAIL SPIGOT FRONT", "SPIGOT - TOP RAIL SPIGOT FRONT", "RIVNUT - TOP RAIL SPIGOT BACK", "SPIGOT - TOP RAIL SPIGOT BACK", "STOP WASHER - BACK STILE CORNER 1", "RIVNUT - BACK STILE CORNER 1", "STOP WASHER - BACK STILE CORNER 2", "STOP WASHER - BACK STILE CORNER 3", "RIVNUT - BACK STILE CORNER 2", "RIVNUT - BACK STILE CORNER 3"
